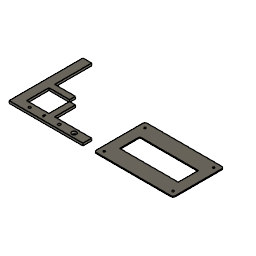
Fit_tests (Autodesk Fusion 360 design; units mm, degrees)
part number: 2026-10-18-19-33-59-696
part number: 2026-10-18-19-33-59-935
part number: 2026-10-18-19-34-00-383
Autodesk Fusion 360 part; units mm, degrees
sketch "100 mm X arm sketch" plane through (0, 0, 0) normal (0, 0, 1) x (1, 0, 0) in component "XY 100mm and hole calibration"
  line L0 (0, 0) -> (100, 0)
  line L1 (100, 0) -> (100, 12)
  line L2 (100, 12) -> (0, 12)
  line L3 (0, 12) -> (0, 0)
extrude "100 mm X arm" add sketch "100 mm X arm sketch" along normal blind 3.2 makes body 1 in component "XY 100mm and hole calibration"
sketch "100 mm Y arm sketch" plane through (0, 0, 0) normal (0, 0, 1) x (1, 0, 0) in component "XY 100mm and hole calibration"
  line L0 (0, 0) -> (12, 0)
  line L1 (12, 0) -> (12, 100)
  line L2 (12, 100) -> (0, 100)
  line L3 (0, 100) -> (0, 0)
extrude "100 mm Y arm" add sketch "100 mm Y arm sketch" along normal blind 3.2 bodies 1 in component "XY 100mm and hole calibration"
ref_plane "WorkPlane1" through (0, 0, -0.1) normal (0, 0, 1) x (1, 0, 0) in component "XY 100mm and hole calibration"
sketch "Hole 3.2 sketch" plane through (0, 0, -0.1) normal (0, 0, 1) x (1, 0, 0) in component "XY 100mm and hole calibration"
  circle A0 centre (22, 6) radius 1.6
extrude "Hole 3.2" cut sketch "Hole 3.2 sketch" along normal blind 3.4 bodies 1 in component "XY 100mm and hole calibration"
ref_plane "WorkPlane2" through (0, 0, -0.1) normal (0, 0, 1) x (1, 0, 0) in component "XY 100mm and hole calibration"
sketch "Hole 3.4 sketch" plane through (0, 0, -0.1) normal (0, 0, 1) x (1, 0, 0) in component "XY 100mm and hole calibration"
  circle A0 centre (42, 6) radius 1.7
extrude "Hole 3.4" cut sketch "Hole 3.4 sketch" along normal blind 3.4 bodies 1 in component "XY 100mm and hole calibration"
ref_plane "WorkPlane3" through (0, 0, -0.1) normal (0, 0, 1) x (1, 0, 0) in component "XY 100mm and hole calibration"
sketch "Hole 3.6 sketch" plane through (0, 0, -0.1) normal (0, 0, 1) x (1, 0, 0) in component "XY 100mm and hole calibration"
  circle A0 centre (62, 6) radius 1.8
extrude "Hole 3.6" cut sketch "Hole 3.6 sketch" along normal blind 3.4 bodies 1 in component "XY 100mm and hole calibration"
ref_plane "WorkPlane4" through (0, 0, -0.1) normal (0, 0, 1) x (1, 0, 0) in component "XY 100mm and hole calibration"
sketch "Hole 6.3 sketch" plane through (0, 0, -0.1) normal (0, 0, 1) x (1, 0, 0) in component "XY 100mm and hole calibration"
  circle A0 centre (82, 6) radius 3.15
extrude "Hole 6.3" cut sketch "Hole 6.3 sketch" along normal blind 3.4 bodies 1 in component "XY 100mm and hole calibration"
sketch "40 mm X reference sketch" plane through (0, 0, 0) normal (0, 0, 1) x (1, 0, 0) in component "XY 100mm and hole calibration"
  line L0 (0, 42) -> (40, 42)
  line L1 (40, 42) -> (40, 50)
  line L2 (40, 50) -> (0, 50)
  line L3 (0, 50) -> (0, 42)
extrude "40 mm X reference" add sketch "40 mm X reference sketch" along normal blind 3.2 bodies 1 in component "XY 100mm and hole calibration"
sketch "40 mm Y reference sketch" plane through (0, 0, 0) normal (0, 0, 1) x (1, 0, 0) in component "XY 100mm and hole calibration"
  line L0 (42, 0) -> (50, 0)
  line L1 (50, 0) -> (50, 40)
  line L2 (50, 40) -> (42, 40)
  line L3 (42, 40) -> (42, 0)
extrude "40 mm Y reference" add sketch "40 mm Y reference sketch" along normal blind 3.2 bodies 1 in component "XY 100mm and hole calibration"
sketch "LCD fit plate sketch" plane through (0, 0, 0) normal (0, 0, 1) x (1, 0, 0) in component "LCD 93x55 mounting fit coupon"
  line L0 (118, 0) -> (219, 0)
  line L1 (222, 3) -> (222, 66)
  line L2 (219, 69) -> (118, 69)
  line L3 (115, 66) -> (115, 3)
  arc A0 (219, 0) -> (222, 3) centre (219, 3) ccw
  arc A1 (222, 66) -> (219, 69) centre (219, 66) ccw
  arc A2 (118, 69) -> (115, 66) centre (118, 66) ccw
  arc A3 (115, 3) -> (118, 0) centre (118, 3) ccw
extrude "LCD fit plate" add sketch "LCD fit plate sketch" along normal blind 1.2 separate body makes body 2 in component "LCD 93x55 mounting fit coupon"
ref_plane "WorkPlane1" through (0, 0, -0.1) normal (0, 0, 1) x (1, 0, 0) in component "LCD 93x55 mounting fit coupon"
sketch "LCD test viewing window sketch" plane through (0, 0, -0.1) normal (0, 0, 1) x (1, 0, 0) in component "LCD 93x55 mounting fit coupon"
  line L0 (129, 21) -> (208, 21)
  line L1 (208, 21) -> (208, 48)
  line L2 (208, 48) -> (129, 48)
  line L3 (129, 48) -> (129, 21)
extrude "LCD test viewing window" cut sketch "LCD test viewing window sketch" along normal blind 1.4 bodies 2 in component "LCD 93x55 mounting fit coupon"
ref_plane "WorkPlane2" through (0, 0, -0.1) normal (0, 0, 1) x (1, 0, 0) in component "LCD 93x55 mounting fit coupon"
sketch "LCD pitch check 93x55 sketch" plane through (0, 0, -0.1) normal (0, 0, 1) x (1, 0, 0) in component "LCD 93x55 mounting fit coupon"
  circle A0 centre (122, 7) radius 1.25
  circle A1 centre (215, 7) radius 1.25
  circle A2 centre (122, 62) radius 1.25
  circle A3 centre (215, 62) radius 1.25
extrude "LCD pitch check 93x55" cut sketch "LCD pitch check 93x55 sketch" along normal blind 1.4 bodies 2 in component "LCD 93x55 mounting fit coupon"
component "XY 100mm and hole calibration" placed x (1, 0, 0) y (0, 1, 0) z (0, 0, 1) at (0, 0, 0)
component "LCD 93x55 mounting fit coupon" placed x (1, 0, 0) y (0, 1, 0) z (0, 0, 1) at (0, 0, 0)
